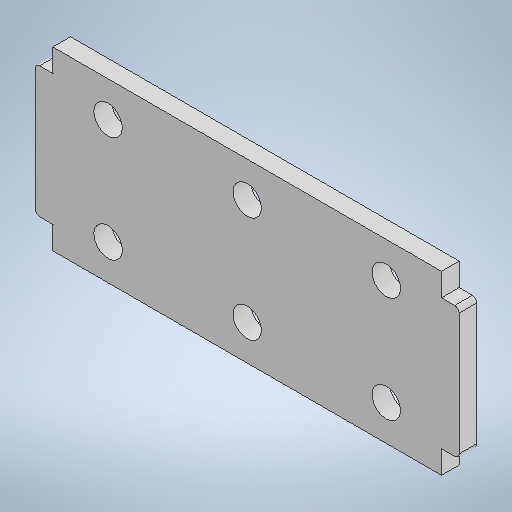
# Autodesk Inventor part: plate_ppm
Saved by Autodesk Inventor 2025.3 (Build 293356000, 356)
## iProperties
Created: 2026-10-27
Part Number: plate_ppm
Material: 一般
Document SubType Name: Modeling
Designer: yunto
Density: 1 g/cm^3
Appearance: 既定
Author: yunto
Autodesk Inventor part; units mm, degrees
ref_plane "YZ Plane" through (0, 0, 0) normal (1, 0, 0) x (0, 1, 0)
ref_plane "XZ Plane" through (0, 0, 0) normal (0, 1, 0) x (-1, 0, 0)
ref_plane "XY Plane" through (0, 0, 0) normal (0, 0, 1) x (1, 0, 0)
sketch "スケッチ1" plane through (0, 0, 0) normal (0, 0, 1) x (1, 0, 0)
  line L0 (22, -10) -> (-22, -10)
  line L1 (-22, -10) -> (-22, 10)
  line L2 (-22, 10) -> (22, 10)
  line L3 (22, 10) -> (22, -10)
  line L4 (22, -10) -> (-22, 10) construction
  line L5 (-22, -10) -> (22, 10) construction
  line L6 (15.75, -6) -> (-15.75, -6) construction
  line L7 (-15.75, -6) -> (-15.75, 6) construction
  line L8 (-15.75, 6) -> (15.75, 6) construction
  line L9 (15.75, 6) -> (15.75, -6) construction
  line L10 (15.75, -6) -> (-15.75, 6) construction
  line L11 (-15.75, -6) -> (15.75, 6) construction
  circle A0 centre (-15.75, 6) radius 1.6
  circle A1 centre (-15.75, -6) radius 1.6
  circle A2 centre (15.75, -6) radius 1.6
  circle A3 centre (15.75, 6) radius 1.6
  line L12 (-24, -7.4) -> (-22, -7.4)
  line L13 (-22, -7.4) -> (-22, 7.4)
  line L14 (-22, 7.4) -> (-24, 7.4)
  line L15 (-24, 7.4) -> (-24, -7.4)
  line L16 (-24, -7.4) -> (-22, 7.4) construction
  line L17 (-22, -7.4) -> (-24, 7.4) construction
  line L18 (24, -7.4) -> (22, -7.4)
  line L19 (22, -7.4) -> (22, 7.4)
  line L20 (22, 7.4) -> (24, 7.4)
  line L21 (24, 7.4) -> (24, -7.4)
  line L22 (24, -7.4) -> (22, 7.4) construction
  line L23 (22, -7.4) -> (24, 7.4) construction
  line L24 (0, 6) -> (0, -6) construction
  circle A4 centre (0, 6) radius 1.6
  circle A5 centre (0, -6) radius 1.6
  line L25 (-23, 0) -> (-22, 0) construction
  line L26 (19, -1) -> (-19, -1)
  line L27 (-19, -1) -> (-19, 1)
  line L28 (-19, 1) -> (19, 1)
  line L29 (19, 1) -> (19, -1)
  line L30 (19, -1) -> (-19, 1) construction
  line L31 (-19, -1) -> (19, 1) construction
  point P0 (0, 0)
  point P1 (23, 0)
  dimension "d0" = 3.2
  dimension "d1" = 12
  dimension "d2" = 20
  dimension "d3" = 2
  dimension "d4" = 14.8
  dimension "d7" = 3.2
  dimension "d8" = 6.25
  dimension "d9" = 44
  dimension "d10" = 12
  dimension "d12" = 5
  dimension "d13" = 5
  constraints: 64 end point, 14 midpoint, 10 parallel, 6 centre point, 6 coincident, 6 horizontal, 5 perpendicular, 4 equal radius, 3 collinear, 2 point on line, 1 vertical
  measures "d0" diameter of A0
  measures "d1" distance of L6.end L7.end
  measures "d2" distance of L0.end L1.end
  measures "d3" distance of L12.start L12.end
  measures "d4" distance of L14.end L12.start
  measures "d7" diameter of A4
  measures "d8" distance between parallel lines of L1 L7
  measures "d9" distance of L1.end L2.end
  measures "d10" distance of L24.start L24.end
  measures "d12" distance between parallel lines of L15 L27
  measures "d13" distance from line of L7.end L28
extrude "押し出し1" add sketch "スケッチ1" along normal blind 2 contours L0 L1 L2 L3 | L3 L20 L21 L18 | L12 L15 L14 L1 | L26 L27 L28 L29
fillet "フィレット1" radius 0.5 4 edges at (-24, -7.4, 1) (-24, 7.4, 1) (24, -7.4, 1) (24, 7.4, 1)
